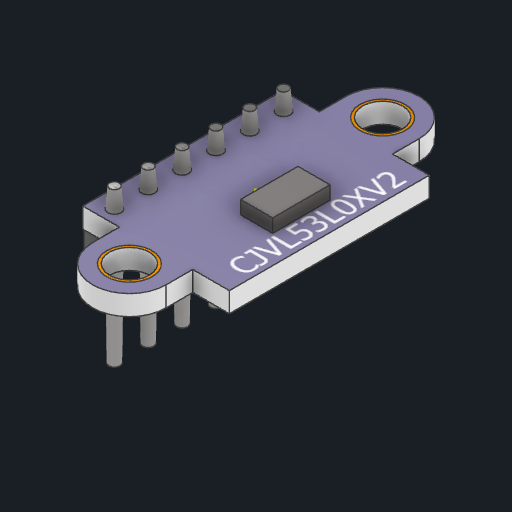
# Autodesk Inventor part: VL53L0X
Saved by Autodesk Inventor 2026.2 (Build 302298010, 298A)
## iProperties
Created: 2026-04-25
Part Number: VL53L0X
Material: PPS 플라스틱
Document SubType Name: Modeling
Designer: work
Density: 1.637 g/cm^3
Appearance: 매끄러움 - 흰색
Author: work
Autodesk Inventor part; units mm, degrees
ref_plane "YZ Plane" through (0, 0, 0) normal (1, 0, 0) x (0, 1, 0)
ref_plane "XZ Plane" through (0, 0, 0) normal (0, 1, 0) x (-1, 0, 0)
ref_plane "XY Plane" through (0, 0, 0) normal (0, 0, 1) x (1, 0, 0)
sketch "스케치1" plane through (0, 0, 0) normal (0, 1, 0) x (-1, 0, 0)
  line L0 (-5.5, 7.5) -> (5.5, 7.5)
  line L1 (5.5, 7.5) -> (5.5, -7.5)
  line L2 (5.5, -7.5) -> (-5.5, -7.5)
  line L3 (-5.5, -7.5) -> (-5.5, 7.5)
  line L4 (-5.5, 7.5) -> (5.5, -7.5) construction
  line L5 (5.5, 7.5) -> (-5.5, -7.5) construction
  line L6 (0, 9.5) -> (0, -9.5) construction
  line L7 (0, 9.5) -> (0, -9.5) construction
  line L8 (-2.75, 9.5) -> (-2.75, -9.5)
  line L9 (2.75, -9.5) -> (2.75, 9.5)
  arc A0 (2.75, 9.5) -> (-2.75, 9.5) centre (0, 9.5) ccw
  arc A1 (-2.75, -9.5) -> (2.75, -9.5) centre (0, -9.5) ccw
  circle A2 centre (0, 9.5) radius 1.5
  circle A3 centre (0, -9.5) radius 1.5
  point P0 (0, 0)
  point P1 (0, 0)
  point P2 (2.75, 7.5)
  point P3 (-2.75, 7.5)
  point P4 (-2.75, -7.5)
  point P5 (2.75, -7.5)
  dimension "d0" = 11
  dimension "d1" = 15
  dimension "d2" = 19
  dimension "d3" = 5.5
  dimension "d4" = 3
  dimension "d5" = 3
  constraints: 22 end point, 6 midpoint, 4 centre point, 4 equal length, 4 point on circle, 4 tangent, 2 coincident, 1 horizontal, 1 perpendicular, 1 vertical
  measures "d0" distance of L1.end L2.end
  measures "d1" distance of L0.end L1.end
  measures "d2" distance of L6.start L6.end
  measures "d3" diameter of A1
  measures "d4" diameter of A2
  measures "d5" diameter of A3
extrude "돌출1" add sketch "스케치1" along normal blind 1.5
sketch "스케치2" plane through (0, 1.5, 0) normal (0, 1, 0) x (1, 0, 0)
  line L0 (5.5, -7.5) -> (5.5, 7.5) projected
  line L1 (5.5, 0) -> (-5.5, 0)
  line L2 (-5.5, 7.5) -> (-5.5, -7.5) projected
  line L3 (3.4, -2.15) -> (1, -2.15)
  line L4 (1, -2.15) -> (1, 2.15)
  line L5 (1, 2.15) -> (3.4, 2.15)
  line L6 (3.4, 2.15) -> (3.4, -2.15)
  line L7 (3.4, -2.15) -> (1, 2.15) construction
  line L8 (1, -2.15) -> (3.4, 2.15) construction
  point P0 (0, 0)
  point P1 (2.2, 0)
  dimension "d8" = 2.4
  dimension "d9" = 4.3
  dimension "d10" = 4.5
  constraints: 14 end point, 4 midpoint, 2 parallel, 1 horizontal, 1 perpendicular, 1 point on line
  measures "d8" distance of L4.end L5.end
  measures "d9" distance of L3.end L4.end
  measures "d10" distance between parallel lines of L0 L4
extrude "돌출2" add sketch "스케치2" along normal blind 1
sketch "스케치3" plane through (0, 0, 0) normal (0, -1, 0) x (1, 0, 0)
  line L0 (0, 0) -> (-5.5, 0)
  line L1 (-5.5, -7.5) -> (-5.5, 7.5) projected
  line L2 (-3.1, 7.45) -> (-5.5, 7.45)
  line L3 (-5.5, 7.45) -> (-5.5, -7.45)
  line L4 (-5.5, -7.45) -> (-3.1, -7.45)
  line L5 (-3.1, -7.45) -> (-3.1, 7.45)
  line L6 (-3.1, 7.45) -> (-5.5, -7.45) construction
  line L7 (-5.5, 7.45) -> (-3.1, -7.45) construction
  line L8 (-5.45, -7.45) -> (-5.45, 7.45)
  point P0 (-4.3, 0)
  point P1 (-5.5, 7.45)
  dimension "d13" = 2.4
  dimension "d14" = 14.9
  dimension "d17" = 0.05
  constraints: 16 end point, 4 point on line, 3 midpoint, 2 parallel, 2 perpendicular, 1 horizontal
  measures "d13" distance of L3.end L4.end
  measures "d14" distance of L4.end L2.start
  measures "d17" distance between parallel lines of L1 L8
extrude "돌출3" add sketch "스케치3" along normal blind 1.5 contours L5 L4 L8 L0 | L0 L8 L2 L5
sketch "스케치4" plane through (0, 1.5, 0) normal (0, 1, 0) x (1, 0, 0)
  line L0 (1, 2.15) -> (3.4, 2.15) projected
  line L1 (3.4, 2.15) -> (3.4, -2.15) projected
  line L2 (3.4, -2.15) -> (1, -2.15) projected
  line L3 (1, -2.15) -> (1, 2.15) projected
  arc A0 (-2.75, -9.5) -> (2.75, -9.5) centre (0, -9.5) ccw projected
  line L4 (2.75, -9.5) -> (2.75, -7.5) projected
  line L5 (2.75, -7.5) -> (5.5, -7.5) projected
  line L6 (5.5, -7.5) -> (5.5, 7.5) projected
  line L7 (5.5, 7.5) -> (2.75, 7.5) projected
  line L8 (2.75, 7.5) -> (2.75, 9.5) projected
  arc A1 (2.75, 9.5) -> (-2.75, 9.5) centre (0, 9.5) ccw projected
  line L9 (-2.75, 9.5) -> (-2.75, 7.5) projected
  line L10 (-2.75, 7.5) -> (-5.5, 7.5) projected
  line L11 (-5.5, 7.5) -> (-5.5, -7.5) projected
  line L12 (-5.5, -7.5) -> (-2.75, -7.5) projected
  line L13 (-2.75, -7.5) -> (-2.75, -9.5) projected
  circle A2 centre (0, 9.5) radius 1.5 projected
  circle A3 centre (0, -9.5) radius 1.5 projected
  circle A4 centre (0, 9.5) radius 1.7
  circle A5 centre (0, -9.5) radius 1.7
  point P0 (0, 0)
  dimension "d18" = 0.2
  dimension "d19" = 0.2
  constraints: 2 centre point, 2 coincident
  measures "d18" radial gap between concentric circles of A4 A2
  measures "d19" radial gap between concentric circles of A5 A3
mark "표식1"
sketch "스케치5" plane through (0, 1.5, 9.5) normal (0, 1, 0) x (1, 0, 0)
  line L0 (-3.1, 2.05) -> (-3.1, 16.95) projected
  line L1 (-5.5, 2) -> (-2.75, 2) projected
  line L2 (-4.125, 2) -> (-4.125, 17) construction
  line L3 (-2.75, 17) -> (-5.5, 17) projected
  circle A0 centre (-4.125, 3) radius 0.5
  circle A1 centre (-4.125, 5.54) radius 0.5
  circle A2 centre (-4.125, 8.08) radius 0.5
  circle A3 centre (-4.125, 10.62) radius 0.5
  circle A4 centre (-4.125, 13.16) radius 0.5
  circle A5 centre (-4.125, 15.7) radius 0.5
  point P0 (0, 9.5)
  dimension "d20" = 1
  dimension "d23" = 2.54
  dimension "d28" = 1
  constraints: 6 centre point, 2 end point, 2 midpoint, 1 point on line, 1 vertical, 10 other
  measures "d20" distance from line of L1 A0.centre
  measures "d23" distance of A0.centre A1.centre
  measures "d28" diameter of A0
extrude "돌출4" add sketch "스케치5" along normal blind 1.5 draft -5
extrude "돌출5" add sketch "스케치5" against normal blind 10 draft -0.5
sketch "스케치6" plane through (0, 1.5, 9.5) normal (0, 1, 0) x (1, 0, 0)
  line L0 (3.571, 3.5398) -> (3.571, 15.8522) construction
  line L1 (3.571, 15.8522) -> (5.1342, 15.8522) construction
  line L2 (5.1342, 15.8522) -> (5.1342, 3.5398) construction
  line L3 (5.1342, 3.5398) -> (3.571, 3.5398) construction
  point P0 (0, 9.5)
  dimension "d1" = 15
  constraints: 2 other
